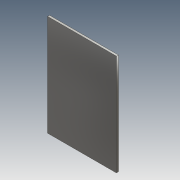
# Autodesk Inventor part: Materials Test Part 2
Saved by Autodesk Inventor 2020 (Build 240168000, 168)
## iProperties
Created: 2019-06-14
Part Number: Materials Test Part 2
Material: Steel, Bright
Document SubType Name: Modeling
Designer: PC
Mass: 13591.4 g
Surface Area: 3672.72 cm^2
Volume: 1731.39 cm^3
Density: 7.85 g/cm^3
Appearance: Steel , Bright
Author: PC
Autodesk Inventor part; units mm, degrees
ref_plane "YZ Plane" through (0, 0, 0) normal (1, 0, 0) x (0, 1, 0)
ref_plane "XZ Plane" through (0, 0, 0) normal (0, 1, 0) x (-1, 0, 0)
sketch "Sketch5" plane through (0, 0, 0) normal (0, 0, 1) x (1, 0, 0)
  line L0 (-12.5, 0) -> (-12.5, 3.2367)
  line L1 (-12.5, 3.2367) -> (-11, 3.2367)
  arc A0 (-11, 3.2367) -> (-8, 6.2367) centre (-11, 6.2367) ccw
  line L2 (-8, 6.2367) -> (-8, 10.2367)
  line L3 (-8, 10.2367) -> (-6.6516, 10.2367)
  line L4 (-6.1516, 10.7367) -> (-6.1516, 13.7367)
  line L5 (-6.6516, 14.2367) -> (-14.1213, 14.2367)
  arc A1 (-16.6213, 16.7277) -> (-14.1213, 14.2367) centre (-14.1213, 16.7367) ccw
  line L6 (-16.6213, 16.7277) -> (-16.6213, 19.4235)
  line L7 (-16.6213, 19.4235) -> (-15.1213, 19.4235)
  line L8 (-15.1213, 19.4235) -> (-15.1213, 17.9235)
  line L9 (-15.1213, 17.9235) -> (-12.1213, 17.9235)
  line L10 (-12.1213, 17.9235) -> (-12.1213, 16.4235)
  line L11 (-12.1213, 16.4235) -> (-2.2741, 16.4235)
  line L12 (-1.2741, 15.4235) -> (-1.2741, 7.841)
  arc A2 (-7.6151, 1.5) -> (-1.2741, 7.841) centre (-7.6151, 7.841) ccw
  line L13 (-11, 1.5) -> (-7.6151, 1.5)
  line L14 (-11, 1.5) -> (-11, 0)
  line L15 (-11, 0) -> (-12.5, 0)
  line L16 (0, 0) -> (0, 19.4235)
  arc A3 (-6.1516, 13.7367) -> (-6.6516, 14.2367) centre (-6.6516, 13.7367) ccw
  arc A4 (-6.6516, 10.2367) -> (-6.1516, 10.7367) centre (-6.6516, 10.7367) ccw
  arc A5 (-1.2741, 15.4235) -> (-2.2741, 16.4235) centre (-2.2741, 15.4235) ccw
  dimension "d5" = 1.5
  dimension "d6" = 1.5
  dimension "d7" = 1.5
  dimension "d8" = 3
  dimension "d9" = 1.5
  dimension "d10" = 4
  dimension "d11" = 0.5
  dimension "d12" = 0.5
  dimension "d13" = 1
  dimension "d14" = 16
  dimension "d15" = 25
  dimension "d16" = 1.5
  dimension "d17" = 4
  dimension "d18" = 2.5
  dimension "d19" = 1.5
  constraints: 34 end point, 13 point on circle, 11 tangent, 10 perpendicular, 6 centre point, 5 vertical, 2 horizontal, 2 horizontal alignment
  measures "d5" distance of L14.end L0.start
  measures "d6" distance of L6.end L7.end
  measures "d7" distance of L7.end L8.end
  measures "d8" distance of L8.end L9.end
  measures "d9" distance of L9.end L10.end
  measures "d10" distance between parallel lines of L5 L3
  measures "d11" radius of A3
  measures "d12" radius of A4
  measures "d13" radius of A5
  measures "d14" diameter of L2 L16
  measures "d15" diameter of L0 L16
  measures "d16" distance of L0.end L1.end
  measures "d17" distance of L2.start L2.end
  measures "d18" radius of A1
  measures "d19" distance of L13.start L14.end
revolve "Revolution3" add sketch "Sketch5" angle 360 about axis through (0, 0, 0) along (0, 1, 0)
fillet "Fillet1" radius 2 3 edges at (12.1213, 17.9235, 0) (12.1213, 16.4235, 0) (15.1213, 17.9235, 0)
fillet "Fillet2" radius 1 1 edges at (8, 10.2367, 0)
fillet "Fillet3" radius 0.5 1 edges at (12.5, 3.2367, 0)
sketch "Sketch6" plane through (0, 16.4235, 0) normal (0, 1, 0) x (1, 0, 0)
  circle A0 centre (0, 0) radius 9.8489
  constraints: 1 centre point, 1 coincident
extrude "Extrusion1" add sketch "Sketch6" along normal blind 200 draft -12 separate body
sketch "Sketch7" plane through (0, 0, 0) normal (0, -1, 0) x (1, 0, 0)
  line L0 (170, -250) -> (-170, -250)
  line L1 (-170, -250) -> (-170, 250)
  line L2 (-170, 250) -> (170, 250)
  line L3 (170, 250) -> (170, -250)
  point P0 (0, 0)
  point P1 (170, 0)
  point P2 (0, -250)
  dimension "d26" = 340
  dimension "d27" = 500
  constraints: 8 end point, 2 midpoint, 2 parallel, 1 horizontal, 1 horizontal alignment, 1 perpendicular, 1 vertical alignment
  measures "d26" distance of L0.start L0.end
  measures "d27" distance of L0.end L1.end
extrude "Extrusion2" add sketch "Sketch7" along normal blind 10 bodies 1
sketch "Sketch8" plane through (0, 0, 0) normal (0, 1, 0) x (1, 0, 0)
  point P0 (0, 0)
ref_plane "Work Plane1" through (0, 0, 119) normal (0, 0, 1) x (1, 0, 0)
sketch "Sketch9" plane through (0, 0, 119) normal (0, 0, 1) x (1, 0, 0)
  circle A0 centre (-111.3967, 60) radius 9.4835
  line L0 (-81.7933, 36) -> (-141, 36)
  line L1 (-111.3967, 36) -> (-111.3967, 60) construction
  point P0 (0, 0)
  constraints: 4 end point, 1 centre point, 1 midpoint, 1 perpendicular, 1 vertical
revolve "Revolution4" add sketch "Sketch9" angle 180 about axis through (-81.7933, 36, 119) along (1, 0, 0) separate body
equation "\"d6\" = d5"
equation "\"d7\" = d6"
equation "\"d9\" = d7"
equation "\"d12\" = d11"
equation "\"d16\" = d9"
equation "\"d19\" = d5"
body "Solid3"
body "Solid4"
body "Solid5"
